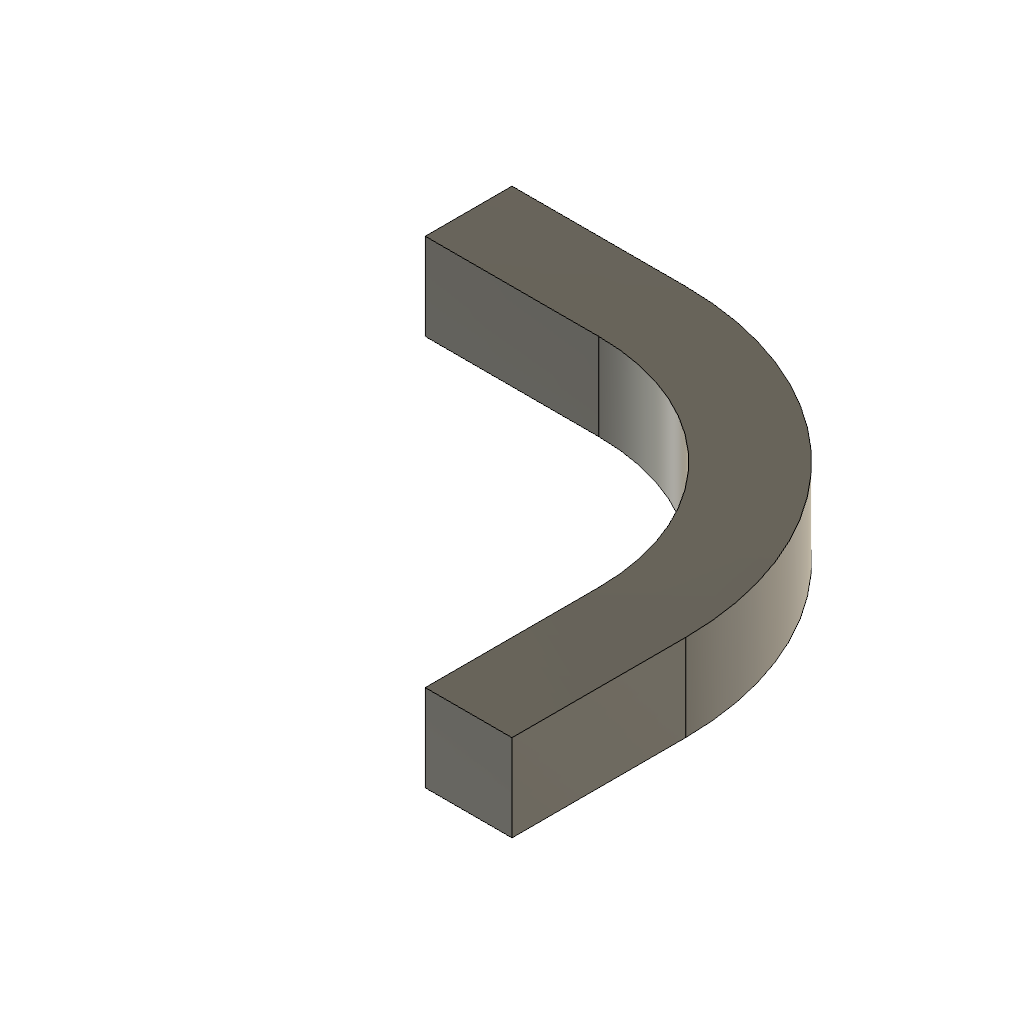
SweepHook (Autodesk Fusion 360 design; units mm, degrees)
part number: 2026-11-12-21-30-37-177
Autodesk Fusion 360 part; units mm, degrees
sketch "Sweep profile" plane through (0, 0, 0) normal (0, 1, 0) x (1, 0, 0)
  line L0 (-5, 0) -> (5, 0)
  line L1 (5, 0) -> (5, -10)
  line L2 (5, -10) -> (-5, -10)
  line L3 (-5, -10) -> (-5, 0)
sketch "Sweep path" plane through (0, 0, 0) normal (0, 0, 1) x (1, 0, 0)
  line L0 (0, 0) -> (0, 20)
  arc A0 (0, 20) -> (-30, 50) centre (-30, 20) ccw
  line L1 (-30, 50) -> (-50, 50)
sweep "Bend sweep" add profiles "Sweep profile" path "Sweep path" along L0 A0 L1 section 1
